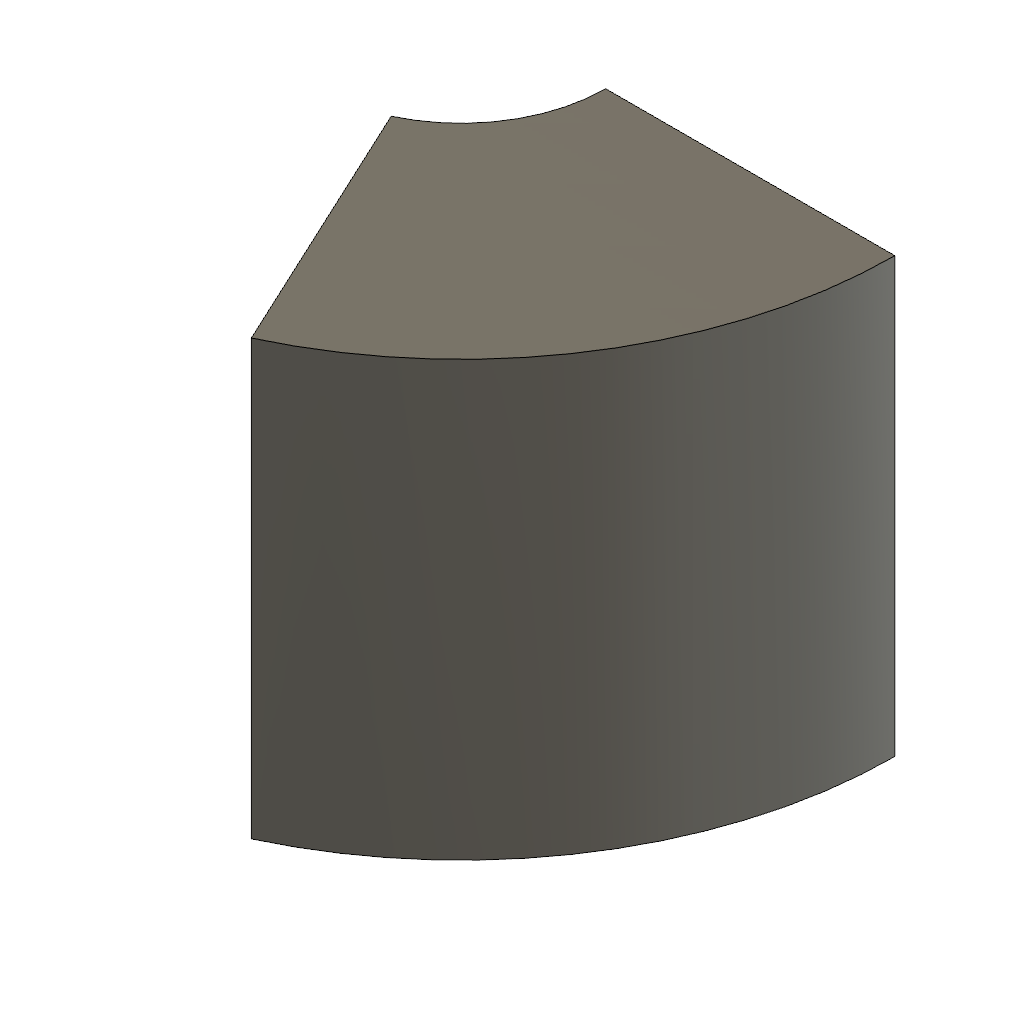
positive (Autodesk Fusion 360 design; units mm, degrees)
part number: 2026-10-20-19-34-05-148
Autodesk Fusion 360 part; units mm, degrees
sketch "ProbeRevolveProfile" plane through (0, 0, 0) normal (0, 0, 1) x (1, 0, 0)
  line L0 (10, 10) -> (30, 10)
  line L1 (30, 10) -> (30, 40)
  line L2 (30, 40) -> (10, 40)
  line L3 (10, 40) -> (10, 10)
revolve "ProbeRevolve" add sketch "ProbeRevolveProfile" angle 65 about axis through (0, 1.75, 0) along (0, -1, 0)
